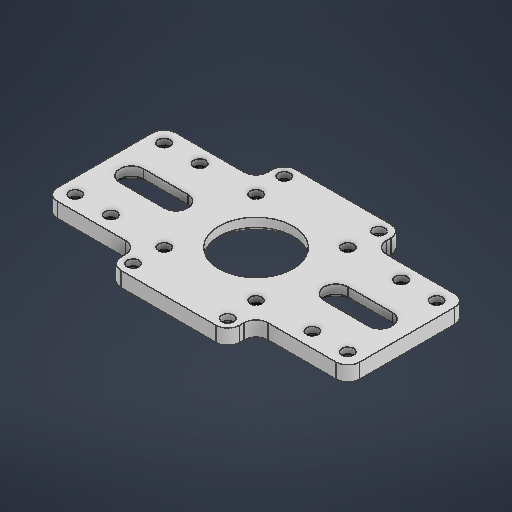
# Autodesk Inventor part: hol
Saved by Autodesk Inventor 2026.2 (Build 302298010, 298A)
## iProperties
Created: 2026-03-21
Part Number: hol
Material: 일반
Document SubType Name: Modeling
Designer: work
Density: 1 g/cm^3
Appearance: 기본값
Author: work
Autodesk Inventor part; units mm, degrees
ref_plane "YZ Plane" through (0, 0, 0) normal (1, 0, 0) x (0, 1, 0)
ref_plane "XZ Plane" through (0, 0, 0) normal (0, 1, 0) x (-1, 0, 0)
ref_plane "XY Plane" through (0, 0, 0) normal (0, 0, 1) x (1, 0, 0)
sketch "스케치1" plane through (0, 0, 0) normal (0, 1, 0) x (-1, 0, 0)
  circle A0 centre (0, 0) radius 12.5
  line L0 (20, 20) -> (-20, 20) construction
  line L1 (-20, 20) -> (-20, -20)
  line L2 (-20, -20) -> (20, -20) construction
  line L3 (20, -20) -> (20, 20)
  line L4 (20, 20) -> (-20, -20) construction
  line L5 (-20, 20) -> (20, -20) construction
  line L6 (15.5, 15.5) -> (-15.5, 15.5) construction
  line L7 (-15.5, 15.5) -> (-15.5, -15.5) construction
  line L8 (-15.5, -15.5) -> (15.5, -15.5) construction
  line L9 (15.5, -15.5) -> (15.5, 15.5) construction
  line L10 (15.5, 15.5) -> (-15.5, -15.5) construction
  line L11 (-15.5, 15.5) -> (15.5, -15.5) construction
  line L12 (0, 0) -> (40, 0) construction
  line L13 (46, 15) -> (34, 15) construction
  line L14 (34, 15) -> (34, -15) construction
  line L15 (34, -15) -> (46, -15) construction
  line L16 (46, -15) -> (46, 15) construction
  line L17 (46, 15) -> (34, -15) construction
  line L18 (34, 15) -> (46, -15) construction
  circle A1 centre (15.5, 15.5) radius 2
  circle A2 centre (15.5, -15.5) radius 2
  circle A3 centre (-15.5, -15.5) radius 2
  circle A4 centre (-15.5, 15.5) radius 2
  circle A5 centre (46, 15) radius 2
  circle A6 centre (34, 15) radius 2
  circle A7 centre (46, -15) radius 2
  circle A8 centre (34, -15) radius 2
  line L19 (20, 20) -> (51, 20)
  line L20 (51, 20) -> (51, -20)
  line L21 (51, -20) -> (20, -20)
  line L22 (20, -20) -> (20, 20)
  line L23 (42, 0) -> (27, 0) construction
  line L24 (42, 4) -> (27, 4)
  line L25 (27, -4) -> (42, -4)
  arc A9 (42, -4) -> (42, 4) centre (42, 0) ccw
  arc A10 (27, 4) -> (27, -4) centre (27, 0) ccw
  line L26 (0, -20) -> (0, 20) construction
  line L27 (0, 0) -> (-40, 0) construction
  line L28 (-46, 15) -> (-34, 15) construction
  line L29 (-34, 15) -> (-34, -15) construction
  line L30 (-34, -15) -> (-46, -15) construction
  line L31 (-46, -15) -> (-46, 15) construction
  line L32 (-46, 15) -> (-34, -15) construction
  line L33 (-34, 15) -> (-46, -15) construction
  circle A11 centre (-46, 15) radius 2
  circle A12 centre (-34, 15) radius 2
  circle A13 centre (-46, -15) radius 2
  circle A14 centre (-34, -15) radius 2
  line L34 (-20, 20) -> (-51, 20)
  line L35 (-51, 20) -> (-51, -20)
  line L36 (-51, -20) -> (-20, -20)
  line L37 (-42, 0) -> (-27, 0) construction
  line L38 (-42, 4) -> (-27, 4)
  line L39 (-27, -4) -> (-42, -4)
  arc A15 (-42, 4) -> (-42, -4) centre (-42, 0) ccw
  arc A16 (-27, -4) -> (-27, 4) centre (-27, 0) ccw
  line L40 (-20, 21.5) -> (20, 21.5) construction
  line L41 (20, 21.5) -> (20, -21.5)
  line L42 (20, -21.5) -> (-20, -21.5) construction
  line L43 (-20, -21.5) -> (-20, 21.5)
  line L44 (-20, 21.5) -> (20, -21.5) construction
  line L45 (20, 21.5) -> (-20, -21.5) construction
  line L46 (20, 21.5) -> (-20, 21.5) construction
  line L47 (-20, 21.5) -> (-20, 29.5)
  line L48 (-20, 29.5) -> (20, 29.5)
  line L49 (20, 29.5) -> (20, 21.5)
  circle A17 centre (-16, 25.5) radius 2
  line L50 (-20, 25.5) -> (20, 25.5) construction
  circle A18 centre (16, 25.5) radius 2
  line L51 (-20, -21.5) -> (-20, -29.5)
  line L52 (-20, -29.5) -> (20, -29.5)
  line L53 (20, -29.5) -> (20, -21.5)
  circle A19 centre (-16, -25.5) radius 2
  line L54 (-20, -25.5) -> (20, -25.5) construction
  circle A20 centre (16, -25.5) radius 2
  point P0 (34.5, 0)
  point P1 (46, 0)
  point P2 (51, 0)
  point P3 (-34.5, 0)
  point P4 (-46, 0)
  point P5 (-51, 0)
  dimension "d0" = 25
  dimension "d1" = 40
  dimension "d2" = 40
  dimension "d3" = 31
  dimension "d4" = 31
  dimension "d5" = 40
  dimension "d6" = 12
  dimension "d7" = 30
  dimension "d8" = 4
  dimension "d9" = 4
  dimension "d10" = 4
  dimension "d11" = 4
  dimension "d12" = 4
  dimension "d13" = 4
  dimension "d14" = 4
  dimension "d15" = 4
  dimension "d16" = 5
  dimension "d17" = 5
  dimension "d19" = 8
  dimension "d20" = 15
  dimension "d21" = 5
  dimension "d22" = 40
  dimension "d23" = 43
  dimension "d24" = 8
  dimension "d25" = 40
  dimension "d26" = 4
  dimension "d27" = 4
  constraints: 114 end point, 29 symmetric about line, 21 centre point, 14 midpoint, 13 coincident, 13 parallel, 9 point on circle, 7 horizontal, 7 perpendicular, 6 point on line, 4 tangent, 9 other
  measures "d0" diameter of A0
  measures "d1" distance of L1.end L2.end
  measures "d2" distance of L2.end L0.start
  measures "d3" distance of L8.end L7.end
  measures "d4" distance of L7.end L6.end
  measures "d5" distance of L12.start L12.end
  measures "d6" distance of L15.end L14.end
  measures "d7" distance of L14.end L13.end
  measures "d8" diameter of A1
  measures "d9" diameter of A2
  measures "d10" diameter of A3
  measures "d11" diameter of A4
  measures "d12" diameter of A5
  measures "d13" diameter of A6
  measures "d14" diameter of A7
  measures "d15" diameter of A8
  measures "d16" distance between parallel lines of L16 L20
  measures "d17" distance between parallel lines of L21 L15
  measures "d19" distance between parallel lines of L25 L24
  measures "d20" distance of L23.end L23.start
  measures "d21" distance of point (46, 0) point (51, 0)
  measures "d22" distance of L41.end L42.end
  measures "d23" distance of L40.end L41.end
  measures "d24" distance of L46.end L47.end
  measures "d25" distance of L47.end L48.end
  measures "d26" diameter of A17
  measures "d27" horizontal distance of L47.end A17.centre
extrude "돌출1" add sketch "스케치1" along normal blind 5
fillet "모깎기1" radius 4 12 edges at (20, 2.5, 20) (20, 2.5, 29.5) (-20, 2.5, 29.5) (-20, 2.5, 20) (-51, 2.5, 20) (-51, 2.5, -20) (-20, 2.5, -29.5) (51, 2.5, 20) (51, 2.5, -20) (20, 2.5, -20) (20, 2.5, -29.5) (-20, 2.5, -20)
chamfer "모따기1" distance 2 angle 45 9 edges at (12.5, 0, 0) (-23, 0, 0) (-34.5, 0, 4) (-46, 0, 0) (-34.5, 0, -4) (34.5, 0, 4) (23, 0, 0) (34.5, 0, -4) (46, 0, 0)
sketch "스케치2" plane through (0, 0, 0) normal (0, -1, 0) x (1, 0, 0)
  circle A0 centre (16, -25.5) radius 2 projected
  circle A1 centre (16, 25.5) radius 2 projected
  circle A2 centre (15.5, 15.5) radius 2 projected
  circle A3 centre (15.5, -15.5) radius 2 projected
  circle A4 centre (-15.5, -15.5) radius 2 projected
  circle A5 centre (-15.5, 15.5) radius 2 projected
  circle A6 centre (-16, 25.5) radius 2 projected
  circle A7 centre (-16, -25.5) radius 2 projected
  circle A8 centre (34, 15) radius 2 projected
  circle A9 centre (34, -15) radius 2 projected
  circle A10 centre (46, -15) radius 2 projected
  circle A11 centre (46, 15) radius 2 projected
  circle A12 centre (-34, -15) radius 2 projected
  circle A13 centre (-34, 15) radius 2 projected
  circle A14 centre (-46, 15) radius 2 projected
  circle A15 centre (-46, -15) radius 2 projected
  arc A16 (16, -29.5) -> (20, -25.5) centre (16, -25.5) ccw projected
  line L0 (20, -24) -> (20, -25.5) projected
  arc A17 (24, -20) -> (20, -24) centre (24, -24) ccw projected
  line L1 (47, -20) -> (24, -20) projected
  arc A18 (47, -20) -> (51, -16) centre (47, -16) ccw projected
  line L2 (51, 16) -> (51, -16) projected
  arc A19 (51, 16) -> (47, 20) centre (47, 16) ccw projected
  line L3 (24, 20) -> (47, 20) projected
  arc A20 (20, 24) -> (24, 20) centre (24, 24) ccw projected
  line L4 (20, 25.5) -> (20, 24) projected
  arc A21 (20, 25.5) -> (16, 29.5) centre (16, 25.5) ccw projected
  line L5 (-16, 29.5) -> (16, 29.5) projected
  arc A22 (-16, 29.5) -> (-20, 25.5) centre (-16, 25.5) ccw projected
  line L6 (-20, 24) -> (-20, 25.5) projected
  arc A23 (-24, 20) -> (-20, 24) centre (-24, 24) ccw projected
  line L7 (-47, 20) -> (-24, 20) projected
  arc A24 (-47, 20) -> (-51, 16) centre (-47, 16) ccw projected
  line L8 (-51, -16) -> (-51, 16) projected
  arc A25 (-51, -16) -> (-47, -20) centre (-47, -16) ccw projected
  line L9 (-24, -20) -> (-47, -20) projected
  arc A26 (-20, -24) -> (-24, -20) centre (-24, -24) ccw projected
  line L10 (-20, -25.5) -> (-20, -24) projected
  arc A27 (-20, -25.5) -> (-16, -29.5) centre (-16, -25.5) ccw projected
  line L11 (16, -29.5) -> (-16, -29.5) projected
  circle A28 centre (0, 0) radius 14.5 projected
  constraints: 16 coincident
hole "구멍1" at (-46, 0, 15) at (-46, 0, -15) at (-34, 0, -15) at (-34, 0, 15) at (-15.5, 0, 15.5) at (-15.5, 0, -15.5) at (-16, 0, -25.5) at (16, 0, -25.5) at (15.5, 0, -15.5) at (-16, 0, 25.5) at (15.5, 0, 15.5) at (16, 0, 25.5) at (34, 0, 15) at (34, 0, -15) at (46, 0, -15) at (46, 0, 15) direction (0, 1, 0) diameter 6.2 depth 3
